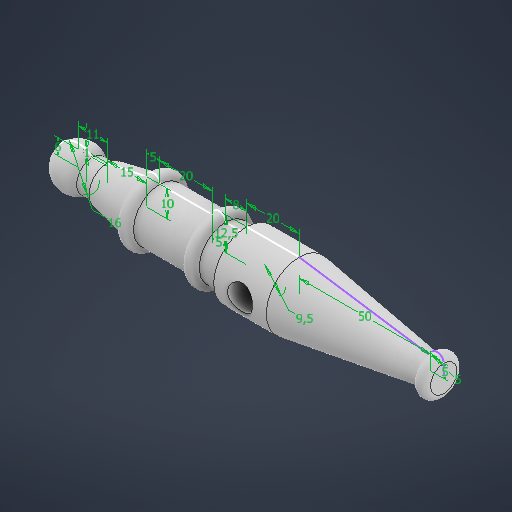
# Autodesk Inventor part: canhazinho
Saved by Autodesk Inventor 2026.2 (Build 302298000, 298)
## iProperties
Created: 2026-08-28
Part Number: canhazinho
Material: Genérico
Document SubType Name: Modeling
Designer: IFSP
Density: 1 g/cm^3
Appearance: Padrão
Author: IFSP
Autodesk Inventor part; units mm, degrees
ref_plane "YZ Plane" through (0, 0, 0) normal (1, 0, 0) x (0, 1, 0)
ref_plane "XZ Plane" through (0, 0, 0) normal (0, 1, 0) x (-1, 0, 0)
ref_plane "XY Plane" through (0, 0, 0) normal (0, 0, 1) x (1, 0, 0)
sketch "Esboço1" plane through (0, 0, 0) normal (0, 0, 1) x (1, 0, 0)
  line L0 (0, 0) -> (139, 0)
  arc A0 (8, 0) -> (-8, 0) centre (0, 0) ccw
  line L1 (0, 0) -> (0, 6)
  line L2 (0, 6) -> (11, 6)
  line L3 (11, 6) -> (11, 0)
  line L4 (11, 6) -> (11, 7)
  line L5 (11, 0) -> (26, 0)
  line L6 (26, 0) -> (26, 10)
  line L7 (26, 10) -> (11, 7)
  line L8 (26, 10) -> (31, 10)
  line L9 (31, 10) -> (31, 0)
  circle A1 centre (28.5, 10) radius 2.5
  line L10 (31, 10) -> (51, 10)
  line L11 (51, 10) -> (56, 10)
  circle A2 centre (53.5, 10) radius 2.5
  line L12 (56, 10) -> (64, 10)
  line L13 (64, 0) -> (64, 12.5)
  line L14 (64, 12.5) -> (84, 12.5)
  line L15 (26, 10) -> (26, 0)
  line L16 (51, 10) -> (51, 0)
  line L17 (56, 10) -> (56, 0)
  line L18 (84, 12.5) -> (84, 0)
  arc A3 (78.75, 0) -> (69.25, 0) centre (74, 0) ccw
  line L19 (84, 0) -> (134, 0)
  line L20 (134, 0) -> (134, 5)
  line L21 (134, 5) -> (84, 12.5)
  line L22 (134, 5) -> (139, 5)
  circle A4 centre (136.5, 5) radius 2.5
  line L23 (139, 5) -> (139, 0)
  line L24 (0, 0) -> (-8, 0)
  circle A5 centre (74, 0) radius 4.75
  point P0 (5.2915, 6)
  dimension "d9" = 16
  dimension "d10" = 6
  dimension "d11" = 11
  dimension "d12" = 1
  dimension "d13" = 15
  dimension "d14" = 10
  dimension "d15" = 5
  dimension "d16" = 20
  dimension "d17" = 5
  dimension "d18" = 8
  dimension "d19" = 12.5
  dimension "d20" = 20
  dimension "d21" = 9.5
  dimension "d22" = 50
  dimension "d23" = 5
  dimension "d24" = 5
  constraints: 48 end point, 9 vertical, 7 perpendicular, 5 centre point, 4 point on circle, 3 horizontal, 3 midpoint, 2 coincident, 1 collinear, 1 point on line, 1 tangent, 18 other
  measures "d9" diameter of A0
  measures "d10" distance of L1.start L1.end
  measures "d11" distance of L1.end L2.end
  measures "d12" distance of L2.end L4.end
  measures "d13" distance of L3.end L5.end
  measures "d14" distance of L5.end L6.end
  measures "d15" distance of L6.end L8.end
  measures "d16" distance of L8.end L10.end
  measures "d17" distance of L10.end L11.end
  measures "d18" distance of L11.end L12.end
  measures "d19" distance of L13.start L13.end
  measures "d20" distance of L13.end L14.end
  measures "d21" diameter of A3
  measures "d22" distance of L18.end L19.end
  measures "d23" distance of L19.end L20.end
  measures "d24" diameter of A4
revolve "Revolução1" add sketch "Esboço1" angle 360 about axis through (0, 0, 0) along (1, 0, 0) contours L1 L2 A0 L0 | L24 A0 L2 L1 | A0 L2 L3 L0 | L3 L4 L7 L6 L0 | L6 A1 L9 L0 | L9 L10 L16 L0 | A1 L8 | L8 A1 | L16 A2 L17 L0 | L17 L12 L13 L0 | A2 L11 | L11 A2 | L13 L14 L18 L0 A3 | L18 L21 L20 L0 | L20 A4 L23 L0 | A4 L22 | L22 A4
extrude "Extrusão1" cut sketch "Esboço1" along normal mid plane 1000 contours A3 L0 | L0 A5
